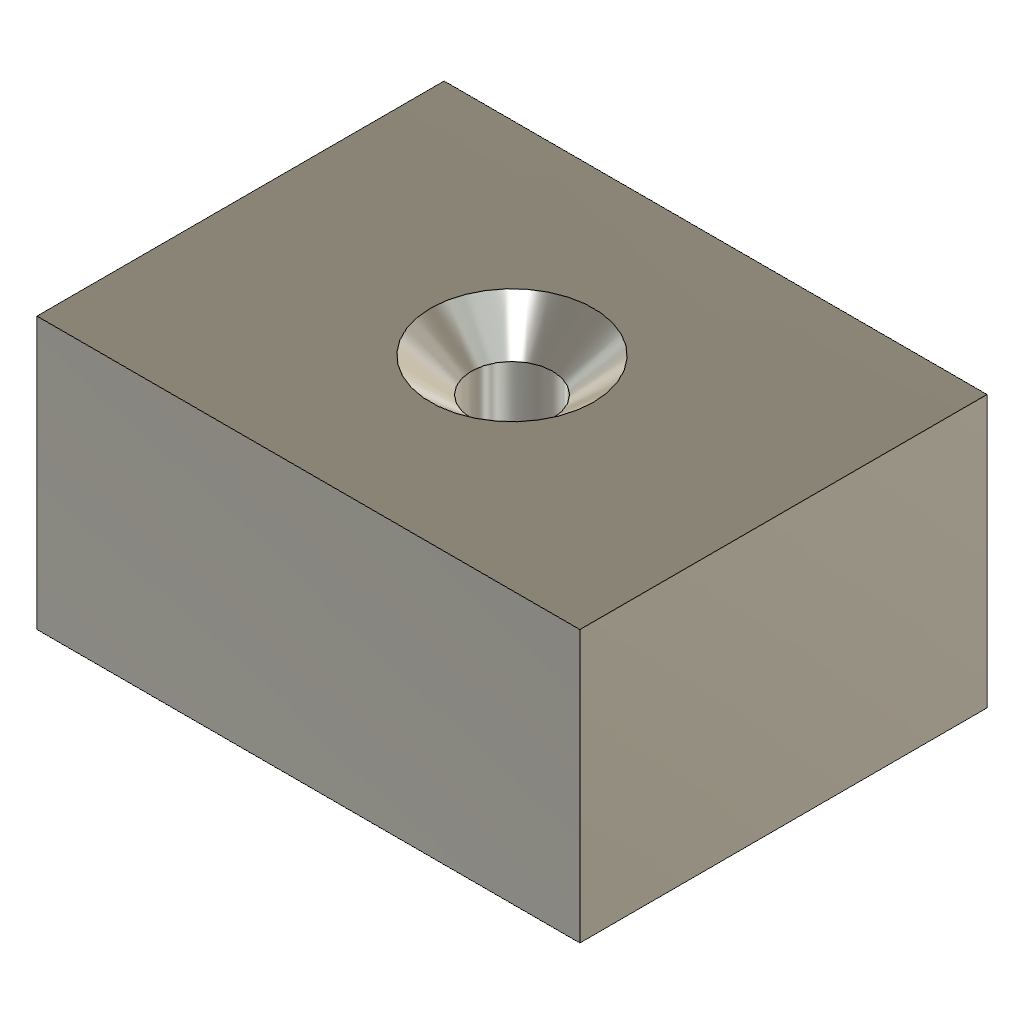
vendor_HoleCountersinkFlat (Autodesk Fusion 360 design; units mm, degrees)
Autodesk Fusion 360 part; units mm, degrees
sketch "Base sketch" plane through (0, 0, 0) normal (0, 0, 1) x (1, 0, 0)
  line L0 (0, 0) -> (40, 0)
  line L1 (40, 0) -> (40, 30)
  line L2 (40, 30) -> (0, 30)
  line L3 (0, 30) -> (0, 0)
extrude "Base extrude" add sketch "Base sketch" along normal blind 20
hole "Top hole" at (20, 15, 20) direction (0, 0, -1) diameter 6 depth 14 tip angle 180 countersink diameter 12 countersink angle 100
equation "height = 20.0 mm"
